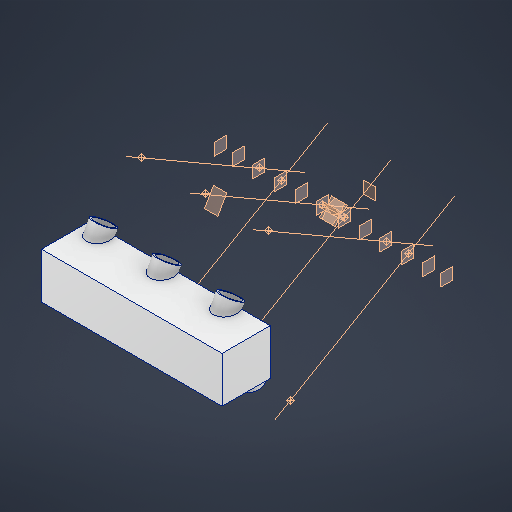
# Autodesk Inventor part: Intake_Manifold_SIMPLIFIED
Saved by Autodesk Inventor 2027.1 (Build 311270010, 270A)
## iProperties
Created: 2026-10-17
Part Number: Intake_Manifold_SIMPLIFIED
Material: Aluminum 6061
Document SubType Name: Modeling
Designer: kashyap
Density: 2.7 g/cm^3
Appearance: Aluminum - Flat
Mass: 5017.47 g
Surface Area: 1279.43 cm^2
Volume: 1858.32 cm^3
Material_Status: Assumed for this reconstruction
Author: kashyap
Autodesk Inventor part; units mm, degrees
derived "V6_Engine_Master.ipt"
ref_plane "Bank_A_Plane" through (0, 0, 0) normal (0, 0.8660254, -0.5) x (-1, 0, 0)
ref_plane "Bank_B_Plane" through (0, 0, 0) normal (0, 0.8660254, 0.5) x (-1, 0, 0)
ref_plane "Bank_A_Perp_Plane" through (0, 0, 0) normal (0, 0.5, 0.8660254) x (-1, 0, 0)
ref_plane "Bank_B_Perp_Plane" through (0, 0, 0) normal (0, -0.5, 0.8660254) x (-1, 0, 0)
ref_plane "Bank_A_Deck_Plane" through (0, 112.9, 195.5485) normal (0, 0.5, 0.8660254) x (-1, 0, 0)
ref_plane "Bank_B_Deck_Plane" through (0, -112.9, 195.5485) normal (0, -0.5, 0.8660254) x (-1, 0, 0)
ref_plane "Cyl_A1_Station_Plane" through (-123.8, 0, 0) normal (1, 0, 0) x (0, 1, 0)
ref_plane "Cyl_A2_Station_Plane" through (-18.3, 0, 0) normal (1, 0, 0) x (0, 1, 0)
ref_plane "Cyl_A3_Station_Plane" through (87.2, 0, 0) normal (1, 0, 0) x (0, 1, 0)
ref_plane "Cyl_B1_Station_Plane" through (-87.2, 0, 0) normal (1, 0, 0) x (0, 1, 0)
ref_plane "Cyl_B2_Station_Plane" through (18.3, 0, 0) normal (1, 0, 0) x (0, 1, 0)
ref_plane "Cyl_B3_Station_Plane" through (123.8, 0, 0) normal (1, 0, 0) x (0, 1, 0)
ref_plane "Main_Bearing_Station_1" through (-158.25, 0, 0) normal (1, 0, 0) x (0, 1, 0)
ref_plane "Main_Bearing_Station_2" through (-52.75, 0, 0) normal (1, 0, 0) x (0, 1, 0)
ref_plane "Main_Bearing_Station_3" through (52.75, 0, 0) normal (1, 0, 0) x (0, 1, 0)
ref_plane "Main_Bearing_Station_4" through (158.25, 0, 0) normal (1, 0, 0) x (0, 1, 0)
ref_plane "Front_Interface" through (-188.25, 0, 0) normal (1, 0, 0) x (0, 1, 0)
ref_plane "Rear_Interface" through (188.25, 0, 0) normal (1, 0, 0) x (0, 1, 0)
ref_plane "Oil_Pan_Plane" through (0, 0, -60) normal (0, 0, 1) x (1, 0, 0)
ref_plane "Intake_Face_A_Plane" through (0, -73.6122, 42.5) normal (0, 0.8660254, -0.5) x (-1, 0, 0)
sketch "SK_Runners_A" plane through (0, -73.6122, 42.5) normal (0, 0.8660254, -0.5) x (-1, 0, 0)
  circle A0 centre (123.8, 248.9693) radius 18
  circle A1 centre (18.3, 248.9693) radius 18
  circle A2 centre (-87.2, 248.9693) radius 18
  dimension "d20" = 36
  dimension "d21" = 36
  dimension "d22" = 36
  constraints: 3 centre point
  measures "d20" diameter of A0
  measures "d21" diameter of A1
  measures "d22" diameter of A2
extrude "Runners_A" add sketch "SK_Runners_A" against normal blind 45
sketch "SK_Runner_Bores_A" plane through (0, -73.6122, 42.5) normal (0, 0.8660254, -0.5) x (-1, 0, 0)
  circle A0 centre (123.8, 248.9693) radius 15
  circle A1 centre (18.3, 248.9693) radius 15
  circle A2 centre (-87.2, 248.9693) radius 15
  dimension "d27" = 30
  dimension "d28" = 30
  dimension "d29" = 30
  constraints: 3 centre point
  measures "d27" diameter of A0
  measures "d28" diameter of A1
  measures "d29" diameter of A2
extrude "Runner_Bores_A" cut sketch "SK_Runner_Bores_A" against normal blind 45
ref_plane "Intake_Face_B_Plane" through (0, 73.6122, 42.5) normal (0, 0.8660254, 0.5) x (-1, 0, 0)
sketch "SK_Runners_B" plane through (0, 73.6122, 42.5) normal (0, 0.8660254, 0.5) x (-1, 0, 0)
  circle A0 centre (87.2, 248.9693) radius 18
  circle A1 centre (-18.3, 248.9693) radius 18
  circle A2 centre (-123.8, 248.9693) radius 18
  dimension "d35" = 36
  dimension "d36" = 36
  dimension "d37" = 36
  constraints: 3 centre point
  measures "d35" diameter of A0
  measures "d36" diameter of A1
  measures "d37" diameter of A2
extrude "Runners_B" add sketch "SK_Runners_B" along normal blind 45
sketch "SK_Runner_Bores_B" plane through (0, 73.6122, 42.5) normal (0, 0.8660254, 0.5) x (-1, 0, 0)
  circle A0 centre (87.2, 248.9693) radius 15
  circle A1 centre (-18.3, 248.9693) radius 15
  circle A2 centre (-123.8, 248.9693) radius 15
  dimension "d40" = 30
  dimension "d41" = 30
  dimension "d42" = 30
  constraints: 3 centre point
  measures "d40" diameter of A0
  measures "d41" diameter of A1
  measures "d42" diameter of A2
extrude "Runner_Bores_B" cut sketch "SK_Runner_Bores_B" along normal blind 45
ref_plane "Plenum_Bottom_Plane" through (0, 0, 255) normal (0, 0, 1) x (1, 0, 0)
sketch "SK_Plenum" plane through (0, 0, 255) normal (0, 0, 1) x (1, 0, 0)
  line L0 (-150, -38) -> (150, -38)
  line L1 (150, -38) -> (150, 38)
  line L2 (150, 38) -> (-150, 38)
  line L3 (-150, 38) -> (-150, -38)
  constraints: 8 end point, 2 parallel, 1 horizontal, 1 perpendicular
extrude "Plenum_SIMPLIFIED" add sketch "SK_Plenum" along normal blind 80
equation "\"d27\" = Intake_Port_Dia"
equation "\"d28\" = Intake_Port_Dia"
equation "\"d29\" = Intake_Port_Dia"
equation "\"d40\" = Intake_Port_Dia"
equation "\"d41\" = Intake_Port_Dia"
equation "\"d42\" = Intake_Port_Dia"
equation "\"d46\" = Plenum_Top_Z - Plenum_Bottom_Z"
equation "\"Intake_Port_Dia\" = 30"
equation "\"Plenum_Top_Z\" = 335"
equation "\"Plenum_Bottom_Z\" = 255"
body "Solid2"
